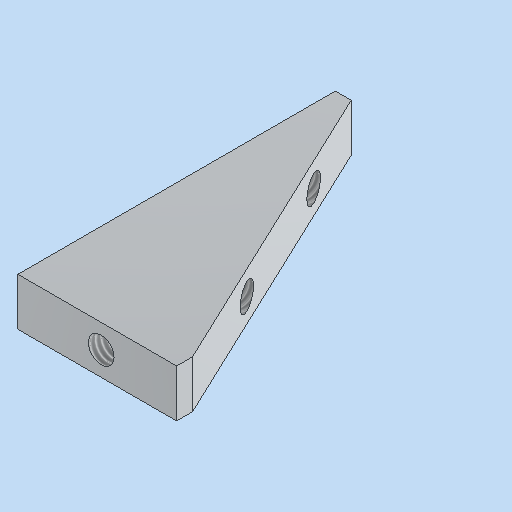
# Autodesk Inventor part: MM0948AN100_G01_165
Saved by Autodesk Inventor 2023.3 (Build 273359000, 359)
## iProperties
Created: 2023-10-27
Part Number: MM0948AN100_G01_165
Material: 3.3547 AlMg4,5Mn0,7 - AW 5083
Description: =<RBPARTNOTITLE2>
Document SubType Name: Modeling
Designer: RIC7AN
Mass: 2.4968 g
Surface Area: 18.2551 cm^2
Volume: 2.4968 cm^3
Density: 1 g/cm^3
Appearance: Aluminium AnP
RBPARTMADEOF: 6 x 40 x 20 (FM)
RBDRAWINGMISSINGSPEC: --
AnP_Kategorie: 1
RBPARTNOTITLE2: Anfertigungsteil
RBSURFACE: anodised colourless
RBPARTNOTITLE1: manufactured part
RBSURFACE2: eloxiert farblos
AnP_Material: =<Material>
RBMATERIAL: =<Material>
RBMATNO: =<Part Number>
RBPARTNO: SIEHE MNR
MaxAbmaße: 6 x 40 x 20 (FM)
Author: RIC7AN
Keywords: =<RBPARTMADEOF>
Comments: =<RBSURFACE2>
Revision Number: 01
Autodesk Inventor part; units mm, degrees
ref_plane "YZ Plane" through (0, 0, 0) normal (1, 0, 0) x (0, 1, 0)
ref_plane "XZ Plane" through (0, 0, 0) normal (0, 1, 0) x (-1, 0, 0)
ref_plane "XY Plane" through (0, 0, 0) normal (0, 0, 1) x (1, 0, 0)
sketch "Skizze1" plane through (0, 0, 0) normal (0, 0, 1) x (1, 0, 0)
  line L0 (0, 0) -> (20, 0)
  line L1 (20, 0) -> (20, 40)
  line L2 (20, 40) -> (0, 40)
  line L3 (0, 40) -> (0, 0)
  line L4 (2, 40) -> (20, 2)
  dimension "d0" = 40
  dimension "d1" = 2
  dimension "d2" = 2
  dimension "d22" = 20
  constraints: 10 end point, 2 parallel, 2 point on line, 1 horizontal, 1 perpendicular
  measures "d0" distance of L2.end L0.start
  measures "d1" distance of L2.end L4.start
  measures "d2" distance of L0.end L4.end
  measures "d22" distance of L1.end L2.end
extrude "Extrusion1" add sketch "Skizze1" along normal mid plane 6 contours L3 L2 L4 L1 L0
sketch "Skizze2" plane through (0, 0, 3) normal (-1, 0, 0) x (0, 0, 1)
  line L0 (-3, 48) -> (-3, -8) projected
  line L1 (-6, 0) -> (0, 0) projected
  point P0 (-3, 0)
  point P1 (-3, 31)
  point P2 (-3, 15)
  dimension "d5" = 16
  dimension "d6" = 15
  constraints: 2 point on line
  measures "d5" distance of point (-3, 15) point (-3, 31)
  measures "d6" distance from line of L1 point (-3, 15)
hole "Bohrung1" at (0, 31, 0) at (0, 15, 0) direction (1, 0, 0) diameter 3.242 end through all thread size "M4x0.7" designation "M4" class "6H" standard "ISO Metric profile"
sketch "Skizze3" plane through (0, 0, 3) normal (0, -1, 0) x (1, 0, 0)
  line L0 (0, 1.2) -> (0, -7.2) projected
  line L1 (-4, -3) -> (24, -3) projected
  point P0 (0, -3)
  point P1 (10.5, -3)
  dimension "d14" = 10.5
  constraints: 1 point on line
  measures "d14" distance from line of point (10.5, -3) L0
hole "Bohrung2" at (10.5, 0, 0) direction (0, 1, 0) diameter 3.242 depth 10 tip angle 118 thread size "M4x0.7" designation "M4" class "6H" standard "ISO Metric profile"
